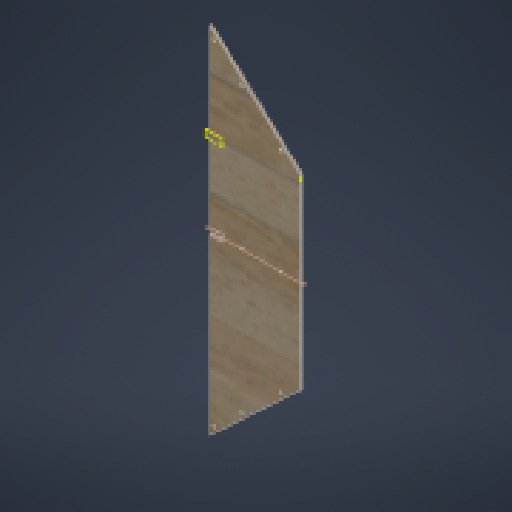
# Autodesk Inventor part: Slope_Front
Saved by Autodesk Inventor 2027.1 (Build 311270010, 270A)
## iProperties
Created: 2026-10-10
Part Number: Slope_Front
Material: 木材 (カエデ材)
Document SubType Name: Modeling
Designer: Takuya Kamada
Density: 0.67 g/cm^3
Appearance: ナチュラル カエデ材 - 光沢 濃い着色
Author: Takuya Kamada
Autodesk Inventor part; units mm, degrees
ref_plane "YZ Plane" through (0, 0, 0) normal (1, 0, 0) x (0, 1, 0)
ref_plane "XZ Plane" through (0, 0, 0) normal (0, 1, 0) x (-1, 0, 0)
ref_plane "XY Plane" through (0, 0, 0) normal (0, 0, 1) x (1, 0, 0)
sketch "スケッチ1" plane through (0, 0, 0) normal (0, 0, 1) x (1, 0, 0)
  line L0 (-5.5149, 0) -> (-5.5149, -8)
  line L1 (0, -8) -> (-85.9977, -8)
  line L2 (-85.9977, 0) -> (0, 0)
  line L3 (0, 332.0277) -> (-85.9977, 332.0277)
  line L4 (-85.9977, 332.0277) -> (-85.9977, -340.0277)
  line L5 (-85.9977, -340.0277) -> (0, -340.0277)
  line L6 (0, -340.0277) -> (0, 332.0277)
  line L7 (4.6323, 0) -> (4.6323, -8)
  line L8 (-85.9977, -190) -> (-85.9977, -198) projected
  point P0 (0, -4)
  point P1 (4.6323, -4)
  point P2 (-85.9977, -194)
  constraints: 16 end point, 3 midpoint, 2 point on line, 1 horizontal, 1 parallel
extrude "押し出し1" add sketch "スケッチ1" along normal blind 2.5
sketch "スケッチ2" plane through (0, 0, 2.5) normal (0, 0, 1) x (1, 0, 0)
  line L0 (-85.9977, 85.1171) -> (0, 4.9012)
  line L1 (0, 332.0277) -> (-85.9977, 332.0277)
  line L2 (-85.9977, 332.0277) -> (-85.9977, -340.0277)
  line L3 (-85.9977, -340.0277) -> (0, -340.0277)
  line L4 (0, -340.0277) -> (0, 332.0277)
  point P0 (0, 0)
  constraints: 10 end point
extrude "押し出し2" cut sketch "スケッチ2" against normal blind 2.5 contours L2 L1 L4 L0
sketch "スケッチ5" plane through (0, 0, 2.5) normal (0, 0, 1) x (1, 0, 0)
  line L0 (0, 4.9012) -> (-85.9977, 85.1171) projected
  line L1 (-85.9977, 85.1171) -> (-85.9977, -340.0277) projected
  line L2 (-85.9977, -340.0277) -> (0, -340.0277) projected
  line L3 (0, -340.0277) -> (0, 4.9012) projected
  line L4 (0, 3.9439) -> (-85.9977, 84.1599)
  line L5 (0, 4.9012) -> (-85.9977, 85.1171) projected
  point P0 (0, 0)
  dimension "d4" = 0.7
  constraints: 2 end point, 2 point on line, 1 parallel
  measures "d4" distance between parallel lines of L4 L0
extrude "押し出し3" cut sketch "スケッチ5" against normal blind 2.5 contours L3 L4 L1 L0
sketch "スケッチ6" plane through (0, 0, 2.5) normal (0, 0, 1) x (1, 0, 0)
  line L0 (0, 3.9439) -> (-85.9977, 84.1599) projected
  line L1 (-85.9977, 84.1599) -> (-85.9977, -340.0277) projected
  line L2 (-85.9977, -340.0277) -> (0, -340.0277) projected
  line L3 (0, -340.0277) -> (0, 3.9439) projected
  line L4 (0, 3.9439) -> (-113.8704, 110.1587)
  line L5 (0, 3.9439) -> (-104.8726, 3.9439)
  line L6 (-104.8726, 3.9439) -> (-104.8726, -340.0277)
  line L7 (-104.8726, -340.0277) -> (0, -340.0277)
  line L8 (0, -340.0277) -> (0, 3.9439)
  line L9 (-104.5843, -190) -> (-85.9977, -190) projected
  line L10 (-104.5843, -190) -> (-104.5843, -198) projected
  line L11 (-85.9977, -198) -> (-104.5843, -198) projected
  line L12 (-85.9977, -190) -> (-85.9977, -198) projected
  line L13 (-104.8726, -190) -> (-104.8726, -198) projected
  line L14 (-104.8726, 3.9439) -> (-104.8726, 101.7659)
  line L15 (-104.5843, 0) -> (-85.9977, 0) projected
  line L16 (-104.5843, 0) -> (-104.5843, -8) projected
  line L17 (-85.9977, -8) -> (-104.5843, -8) projected
  line L18 (-85.9977, 0) -> (-85.9977, -8) projected
  line L19 (-104.8726, 0) -> (-104.5843, 0) projected
  line L20 (-104.8726, 0) -> (-104.8726, -8) projected
  line L21 (-104.5843, -8) -> (-104.8726, -8) projected
  line L22 (-104.5843, 0) -> (-104.5843, -8) projected
  line L23 (-104.8726, -190) -> (-104.5843, -190) projected
  line L24 (-104.8726, -190) -> (-104.8726, -198) projected
  line L25 (-104.5843, -198) -> (-104.8726, -198) projected
  line L26 (-104.5843, -190) -> (-104.5843, -198) projected
  point P0 (0, 0)
  constraints: 12 end point, 3 point on line, 2 parallel, 1 horizontal, 1 perpendicular, 1 vertical
extrude "押し出し4" add sketch "スケッチ6" against normal blind 2.5 contours L1 L5 L14 L4 | L1 L15 L19 L6 L5 | L7 L6 L25 L11 L1 | L1 L9 L23 L6 L21 L17
sketch "スケッチ7" plane through (0, -340.0277, 0) normal (0, -1, 0) x (1, 0, 0)
  line L0 (-5.5149, -36.4635) -> (7.4622, -2.8838) projected
  line L1 (7.4622, -2.8838) -> (3.7311, -1.4419) projected
  line L2 (3.7311, -1.4419) -> (4.6323, 0.89) projected
  line L3 (4.6323, 0.89) -> (0, 2.6802) projected
  line L4 (0, 2.6802) -> (0, 0) projected
  line L5 (0, 0) -> (-85.9977, 0) projected
  line L6 (-85.9977, 0) -> (-85.9977, 2.6802) projected
  line L7 (-85.9977, 2.6802) -> (-104.5843, 2.6802) projected
  line L8 (-104.5843, 2.6802) -> (-104.8726, 1.934) projected
  line L9 (-104.8726, 1.934) -> (-5.5149, -36.4635) projected
  line L10 (-73.0596, -5) -> (-1.9323, -5) projected
  line L11 (-1.9323, -5) -> (-11.1747, -28.9158) projected
  line L12 (-11.1747, -28.9158) -> (-73.0596, -5) projected
  line L13 (0, 0) -> (-104.8726, 0) projected
  line L14 (0, 0) -> (0, 2.5) projected
  line L15 (-104.8726, 2.5) -> (0, 2.5) projected
  line L16 (-104.8726, 2.5) -> (-104.8726, 0) projected
  line L17 (-99.8683, 0) -> (-99.8683, 2.5)
  constraints: 3 point on line, 2 end point, 1 perpendicular
extrude "押し出し5" cut sketch "スケッチ7" against normal up to surface contours L13 L16 L9 | L9 L8 L15 L17 | L16 L15 L8 surface through (0, 3.9439, 2.5) normal (-0.6820976, -0.7312611, 0)
sketch "スケッチ9" plane through (0, 0, 2.5) normal (0, 0, 1) x (1, 0, 0)
  line L0 (-99.8683, -198) -> (-99.8683, -340.0277) projected
  line L1 (-99.8683, -340.0277) -> (0, -340.0277) projected
  line L2 (0, -340.0277) -> (0, 3.9439) projected
  line L3 (0, 3.9439) -> (-99.8683, 97.0979) projected
  line L4 (-99.8683, 97.0979) -> (-99.8683, 0) projected
  line L5 (-99.8683, 0) -> (-85.9977, 0) projected
  line L6 (-85.9977, 0) -> (-85.9977, -8) projected
  line L7 (-85.9977, -8) -> (-99.8683, -8) projected
  line L8 (-99.8683, -8) -> (-99.8683, -190) projected
  line L9 (-99.8683, -190) -> (-85.9977, -190) projected
  line L10 (-85.9977, -190) -> (-85.9977, -198) projected
  line L11 (-85.9977, -198) -> (-99.8683, -198) projected
  line L12 (315.237, -99) -> (-174.8909, -99)
  point P0 (0, 0)
  point P1 (0, -99)
  point P2 (-99.8683, -99)
  constraints: 2 end point, 1 horizontal, 2 other
extrude "押し出し6" cut sketch "スケッチ9" against normal blind 2.5 contours L11 L10 L9 L8 L12 L2 L1 L0
ref_plane "作業平面2" through (-71.4335, -99, 2.5) normal (0, 1, 0) x (1, 0, 0)
sketch "スケッチ10" plane through (0, 0, 2.5) normal (0, 0, 1) x (1, 0, 0)
  line L0 (-99.8683, -99) -> (0, -99) projected
  line L1 (0, -99) -> (0, 3.9439) projected
  line L2 (0, 3.9439) -> (-99.8683, 97.0979) projected
  line L3 (-99.8683, 97.0979) -> (-99.8683, 0) projected
  line L4 (-99.8683, 0) -> (-85.9977, 0) projected
  line L5 (-85.9977, 0) -> (-85.9977, -8) projected
  line L6 (-85.9977, -8) -> (-99.8683, -8) projected
  line L7 (-99.8683, -8) -> (-99.8683, -99) projected
  line L8 (40.0782, -99) -> (-140.2237, -99)
  line L9 (0, -99) -> (0, -201.9439)
  line L10 (0, -201.9439) -> (-99.8683, -295.0979)
  line L11 (-99.8683, -295.0979) -> (-99.8683, -198)
  line L12 (-99.8683, -198) -> (-85.9977, -198)
  line L13 (-85.9977, -198) -> (-85.9977, -190)
  line L14 (-85.9977, -190) -> (-99.8683, -190)
  line L15 (-99.8683, -190) -> (-99.8683, -99)
  point P0 (0, 0)
  constraints: 16 end point, 6 symmetric about line, 2 horizontal alignment, 1 horizontal
extrude "押し出し7" add sketch "スケッチ10" against normal blind 2.5 contours L0 L9 L10 L11 L12 L13 L14 L15
sketch "スケッチ11" plane through (0, 0, 2.5) normal (0, 0, 1) x (1, 0, 0)
  circle A0 centre (-21.4994, -4) radius 1.5 projected
  circle A1 centre (-64.4983, -4) radius 1.5 projected
  circle A2 centre (-64.4983, -194) radius 1.5 projected
  circle A3 centre (-21.4994, -194) radius 1.5 projected
  point P0 (0, 0)
extrude "押し出し8" cut sketch "スケッチ11" against normal blind 2.5
sketch "スケッチ12" plane through (0, 0, 2.5) normal (0, 0, 1) x (1, 0, 0)
  circle A0 centre (-21.4994, -194) radius 1.5 projected
  circle A1 centre (-64.4983, -4) radius 1.5 projected
  circle A2 centre (-64.4983, -194) radius 1.5 projected
  circle A3 centre (-21.4994, -4) radius 1.5 projected
  line L0 (0, -201.9439) -> (0, 3.9439) projected
  line L1 (0, 3.9439) -> (-99.8683, 97.0979) projected
  line L2 (-99.8683, 97.0979) -> (-99.8683, 0) projected
  line L3 (-99.8683, 0) -> (-85.9977, 0) projected
  line L4 (-85.9977, 0) -> (-85.9977, -8) projected
  line L5 (-85.9977, -8) -> (-99.8683, -8) projected
  line L6 (-99.8683, -8) -> (-99.8683, -190) projected
  line L7 (-99.8683, -190) -> (-85.9977, -190) projected
  line L8 (-85.9977, -190) -> (-85.9977, -198) projected
  line L9 (-85.9977, -198) -> (-99.8683, -198) projected
  line L10 (-99.8683, -198) -> (-99.8683, -295.0979) projected
  line L11 (-99.8683, -295.0979) -> (0, -201.9439) projected
  line L12 (337.0582, -99) -> (-305.8184, -99)
  line L13 (-21.4994, -4) -> (-64.4983, -4)
  line L14 (-64.4983, -4) -> (-64.4983, -194)
  line L15 (-64.4983, -194) -> (-21.4994, -194)
  line L16 (-21.4994, -194) -> (-21.4994, -4)
  circle A4 centre (-21.4994, -99) radius 1.5
  circle A5 centre (-64.4983, -99) radius 1.5
  point P0 (0, 0)
  dimension "d17" = 3
  dimension "d18" = 3
  constraints: 10 end point, 2 centre point, 2 horizontal, 2 midpoint, 2 parallel, 1 perpendicular, 2 other
  measures "d17" diameter of A4
  measures "d18" diameter of A5
extrude "押し出し9" cut sketch "スケッチ12" against normal blind 2.5 contours A4 L12 L16 | L16 L12 A4 | L16 A4 L12 | L12 A4 L16 | A5 L14 L12 | L12 L14 A5 | A5 L12 L14 | L12 A5 L14
sketch "スケッチ13" plane through (0, 0, 2.5) normal (0, 0, 1) x (1, 0, 0)
  line L0 (-104.5843, -95) -> (-85.9977, -95) projected
  line L1 (-104.5843, -95) -> (-104.5843, -103) projected
  line L2 (-85.9977, -103) -> (-104.5843, -103) projected
  line L3 (-85.9977, -95) -> (-85.9977, -103) projected
  point P0 (0, 0)
extrude "押し出し10" cut sketch "スケッチ13" against normal blind 2.5
sketch "スケッチ14" plane through (0, 0, 2.5) normal (0, 0, 1) x (1, 0, 0)
  line L0 (-85.9977, -103) -> (-99.8683, -103) projected
  line L1 (-99.8683, -103) -> (-99.8683, -190) projected
  line L2 (-99.8683, -190) -> (-85.9977, -190) projected
  line L3 (-85.9977, -190) -> (-85.9977, -198) projected
  line L4 (-85.9977, -198) -> (-99.8683, -198) projected
  line L5 (-99.8683, -198) -> (-99.8683, -295.0979) projected
  line L6 (-99.8683, -295.0979) -> (0, -201.9439) projected
  line L7 (0, -201.9439) -> (0, 3.9439) projected
  line L8 (0, 3.9439) -> (-99.8683, 97.0979) projected
  line L9 (-99.8683, 97.0979) -> (-99.8683, 0) projected
  line L10 (-99.8683, 0) -> (-85.9977, 0) projected
  line L11 (-85.9977, 0) -> (-85.9977, -8) projected
  line L12 (-85.9977, -8) -> (-99.8683, -8) projected
  line L13 (-99.8683, -8) -> (-99.8683, -95) projected
  line L14 (-99.8683, -95) -> (-85.9977, -95) projected
  line L15 (-85.9977, -95) -> (-85.9977, -103) projected
  circle A0 centre (-21.4994, -99) radius 1.5 projected
  circle A1 centre (-64.4983, -99) radius 1.5 projected
  circle A2 centre (-21.4994, -194) radius 1.5 projected
  circle A3 centre (-64.4983, -4) radius 1.5 projected
  circle A4 centre (-64.4983, -194) radius 1.5 projected
  circle A5 centre (-21.4994, -4) radius 1.5 projected
  line L16 (-21.4994, -99) -> (-21.4994, 23.9979)
  line L17 (-64.4983, -99) -> (-64.4983, 64.1059)
  line L18 (0, -2.8936) -> (-99.8683, 90.2604)
  circle A6 centre (-64.4983, 57.2684) radius 1.5
  circle A7 centre (-21.4994, 17.1604) radius 1.5
  circle A8 centre (-94.8683, 85.5966) radius 1.5
  point P0 (0, 0)
  dimension "d23" = 5
  dimension "d24" = 3
  dimension "d25" = 3
  dimension "d26" = 3
  dimension "d27" = 5
  constraints: 9 point on line, 6 end point, 3 centre point, 2 parallel, 1 vertical
  measures "d23" distance between parallel lines of L18 L8
  measures "d24" diameter of A6
  measures "d25" diameter of A7
  measures "d26" diameter of A8
  measures "d27" horizontal distance of L18.end A8.centre
extrude "押し出し11" cut sketch "スケッチ14" against normal blind 2.5 contours A8 L18 | L18 A8 | A7 L16 L18 | L18 L16 A7 | L18 A7 L16 | L16 A7 L18 | A6 L18 L17 | L17 L18 A6 | L18 L17 A6 | L18 A6 L17
sketch "スケッチ15" plane through (0, 0, 2.5) normal (0, 0, 1) x (1, 0, 0)
  circle A0 centre (-94.8683, 85.5966) radius 1.5 projected
  circle A1 centre (-64.4983, 57.2684) radius 1.5 projected
  circle A2 centre (-21.4994, 17.1604) radius 1.5 projected
  line L0 (-85.9977, -103) -> (-99.8683, -103) projected
  line L1 (-99.8683, -103) -> (-99.8683, -190) projected
  line L2 (-99.8683, -190) -> (-85.9977, -190) projected
  line L3 (-85.9977, -190) -> (-85.9977, -198) projected
  line L4 (-85.9977, -198) -> (-99.8683, -198) projected
  line L5 (-99.8683, -198) -> (-99.8683, -295.0979) projected
  line L6 (-99.8683, -295.0979) -> (0, -201.9439) projected
  line L7 (0, -201.9439) -> (0, 3.9439) projected
  line L8 (0, 3.9439) -> (-99.8683, 97.0979) projected
  line L9 (-99.8683, 97.0979) -> (-99.8683, 0) projected
  line L10 (-99.8683, 0) -> (-85.9977, 0) projected
  line L11 (-85.9977, 0) -> (-85.9977, -8) projected
  line L12 (-85.9977, -8) -> (-99.8683, -8) projected
  line L13 (-99.8683, -8) -> (-99.8683, -95) projected
  line L14 (-99.8683, -95) -> (-85.9977, -95) projected
  line L15 (-85.9977, -95) -> (-85.9977, -103) projected
  circle A3 centre (-21.4994, -99) radius 1.5 projected
  circle A4 centre (-64.4983, -99) radius 1.5 projected
  circle A5 centre (-21.4994, -194) radius 1.5 projected
  circle A6 centre (-64.4983, -4) radius 1.5 projected
  circle A7 centre (-64.4983, -194) radius 1.5 projected
  circle A8 centre (-21.4994, -4) radius 1.5 projected
  line L16 (0, -201.9439) -> (0, 3.9439) projected
  line L17 (0, -99) -> (-85.9977, -99)
  circle A9 centre (-94.8683, -283.5966) radius 1.5
  circle A10 centre (-64.4983, -255.2684) radius 1.5
  circle A11 centre (-21.4994, -215.1604) radius 1.5
  point P0 (0, 0)
  constraints: 3 centre point, 3 symmetric about line, 2 end point, 2 midpoint, 3 other
extrude "押し出し12" cut sketch "スケッチ15" against normal blind 2.5 contours A9 | A10 | A11
sketch "スケッチ16" plane through (0, 0, 2.5) normal (0, 0, 1) x (1, 0, 0)
  circle A0 centre (-94.8683, -283.5966) radius 1.5 projected
  circle A1 centre (-64.4983, -255.2684) radius 1.5 projected
  circle A2 centre (-21.4994, -215.1604) radius 1.5 projected
  circle A3 centre (-94.8683, 85.5966) radius 1.5 projected
  circle A4 centre (-64.4983, 57.2684) radius 1.5 projected
  circle A5 centre (-21.4994, 17.1604) radius 1.5 projected
  line L0 (-85.9977, -103) -> (-99.8683, -103) projected
  line L1 (-99.8683, -103) -> (-99.8683, -190) projected
  line L2 (-99.8683, -190) -> (-85.9977, -190) projected
  line L3 (-85.9977, -190) -> (-85.9977, -198) projected
  line L4 (-85.9977, -198) -> (-99.8683, -198) projected
  line L5 (-99.8683, -198) -> (-99.8683, -295.0979) projected
  line L6 (-99.8683, -295.0979) -> (0, -201.9439) projected
  line L7 (0, -201.9439) -> (0, 3.9439) projected
  line L8 (0, 3.9439) -> (-99.8683, 97.0979) projected
  line L9 (-99.8683, 97.0979) -> (-99.8683, 0) projected
  line L10 (-99.8683, 0) -> (-85.9977, 0) projected
  line L11 (-85.9977, 0) -> (-85.9977, -8) projected
  line L12 (-85.9977, -8) -> (-99.8683, -8) projected
  line L13 (-99.8683, -8) -> (-99.8683, -95) projected
  line L14 (-99.8683, -95) -> (-85.9977, -95) projected
  line L15 (-85.9977, -95) -> (-85.9977, -103) projected
  circle A6 centre (-21.4994, -99) radius 1.5 projected
  circle A7 centre (-64.4983, -99) radius 1.5 projected
  circle A8 centre (-21.4994, -194) radius 1.5 projected
  circle A9 centre (-64.4983, -4) radius 1.5 projected
  circle A10 centre (-64.4983, -194) radius 1.5 projected
  circle A11 centre (-21.4994, -4) radius 1.5 projected
  line L16 (-99.8683, -295.0979) -> (-99.8683, -198) projected
  line L17 (-99.8683, 0) -> (-99.8683, -198)
  point P0 (0, 0)
  constraints: 2 end point, 1 vertical
extrude "押し出し13" add sketch "スケッチ16" against normal blind 2.5 contours L2 L3 L4 L17 | L17 L10 L11 L12 | A8 | A9 | A10 | A11
sketch "スケッチ17" plane through (0, 0, 2.5) normal (0, 0, 1) x (1, 0, 0)
  line L0 (-104.5843, -19) -> (-85.9977, -19) projected
  line L1 (-104.5843, -19) -> (-104.5843, -27) projected
  line L2 (-85.9977, -27) -> (-104.5843, -27) projected
  line L3 (-85.9977, -19) -> (-85.9977, -27) projected
  circle A0 centre (-64.4983, -23) radius 1.5 projected
  circle A1 centre (-21.4994, -23) radius 1.5 projected
  circle A2 centre (-21.4994, -175) radius 1.5 projected
  circle A3 centre (-64.4983, -175) radius 1.5 projected
  line L4 (-104.5843, -171) -> (-85.9977, -171) projected
  line L5 (-104.5843, -171) -> (-104.5843, -179) projected
  line L6 (-85.9977, -179) -> (-104.5843, -179) projected
  line L7 (-85.9977, -171) -> (-85.9977, -179) projected
  point P0 (0, 0)
extrude "押し出し14" cut sketch "スケッチ17" against normal blind 2.5
